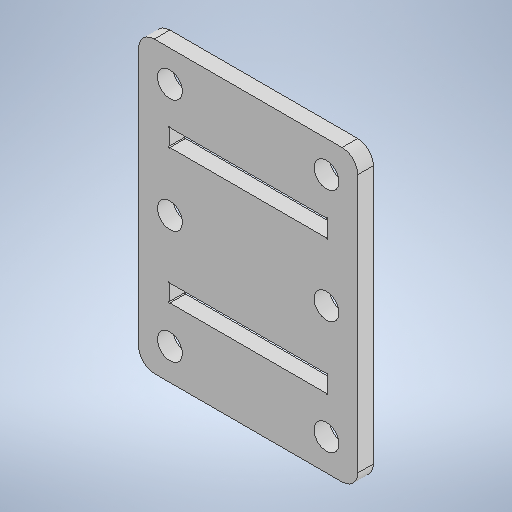
# Autodesk Inventor part: plate_ppp
Saved by Autodesk Inventor 2025.3 (Build 293356000, 356)
## iProperties
Created: 2026-10-27
Part Number: plate_ppp
Material: 一般
Document SubType Name: Modeling
Designer: yunto
Density: 1 g/cm^3
Appearance: 既定
Author: yunto
Autodesk Inventor part; units mm, degrees
ref_plane "YZ Plane" through (0, 0, 0) normal (1, 0, 0) x (0, 1, 0)
ref_plane "XZ Plane" through (0, 0, 0) normal (0, 1, 0) x (-1, 0, 0)
ref_plane "XY Plane" through (0, 0, 0) normal (0, 0, 1) x (1, 0, 0)
sketch "スケッチ1" plane through (0, 0, 0) normal (0, 0, 1) x (1, 0, 0)
  line L0 (14, -18.5) -> (-14, -18.5)
  line L1 (-14, -18.5) -> (-14, 18.5)
  line L2 (-14, 18.5) -> (14, 18.5)
  line L3 (14, 18.5) -> (14, -18.5)
  line L4 (14, -18.5) -> (-14, 18.5) construction
  line L5 (-14, -18.5) -> (14, 18.5) construction
  line L6 (-10, -14.5) -> (10, -14.5) construction
  line L7 (10, -14.5) -> (10, 14.5) construction
  line L8 (10, 14.5) -> (-10, 14.5) construction
  line L9 (-10, 14.5) -> (-10, -14.5) construction
  line L10 (-10, -14.5) -> (10, 14.5) construction
  line L11 (10, -14.5) -> (-10, 14.5) construction
  circle A0 centre (-10, 14.5) radius 1.6
  circle A1 centre (10, 14.5) radius 1.6
  circle A2 centre (-10, -14.5) radius 1.6
  circle A3 centre (10, -14.5) radius 1.6
  circle A4 centre (-10, 0) radius 1.6
  circle A5 centre (10, 0) radius 1.6
  line L12 (10.1, -9.7) -> (-10.1, -9.7)
  line L13 (-10.1, -9.7) -> (-10.1, 9.7)
  line L14 (-10.1, 9.7) -> (10.1, 9.7)
  line L15 (10.1, 9.7) -> (10.1, -9.7)
  line L16 (10.1, -9.7) -> (-10.1, 9.7) construction
  line L17 (-10.1, -9.7) -> (10.1, 9.7) construction
  line L18 (10.1, -7.5) -> (-10.1, -7.5)
  line L19 (-10.1, -7.5) -> (-10.1, 7.5)
  line L20 (-10.1, 7.5) -> (10.1, 7.5)
  line L21 (10.1, 7.5) -> (10.1, -7.5)
  line L22 (10.1, -7.5) -> (-10.1, 7.5) construction
  line L23 (-10.1, -7.5) -> (10.1, 7.5) construction
  circle A6 centre (10.1, 9.7) radius 0.1
  circle A7 centre (10.1, 7.5) radius 0.1
  circle A8 centre (-10.1, 9.7) radius 0.1
  circle A9 centre (-10.1, 7.5) radius 0.1
  circle A10 centre (-10.1, -7.5) radius 0.1
  circle A11 centre (10.1, -7.5) radius 0.1
  circle A12 centre (10.1, -9.7) radius 0.1
  circle A13 centre (-10.1, -9.7) radius 0.1
  point P0 (0, 0)
  point P1 (10.1, -7.5)
  point P2 (10.1, -7.6)
  point P3 (10.1, -9.6)
  point P4 (10, -9.7)
  point P5 (-10, -9.7)
  point P6 (-10.1, -9.6)
  point P7 (-10.1, -7.6)
  point P8 (-10, -7.5)
  point P9 (10, -7.5)
  point P10 (10, 7.5)
  point P11 (-10, 7.5)
  point P12 (-10.1, 7.6)
  point P13 (-10.1, 9.6)
  point P14 (-10, 9.7)
  point P15 (10, 9.7)
  point P16 (10.1, 9.6)
  point P17 (10.1, 7.6)
  dimension "d0" = 3.2
  dimension "d1" = 20
  dimension "d2" = 29
  dimension "d3" = 37
  dimension "d4" = 28
  dimension "d5" = 19.4
  dimension "d6" = 20.2
  dimension "d9" = 2.2
  dimension "d11" = 0.2
  constraints: 48 end point, 14 centre point, 12 equal radius, 11 coincident, 10 midpoint, 8 parallel, 4 horizontal, 4 perpendicular, 3 point on line
  measures "d0" diameter of A0
  measures "d1" distance of L7.end L8.end
  measures "d2" distance of L8.end L6.start
  measures "d3" distance of L0.end L1.end
  measures "d4" distance of L1.end L2.end
  measures "d5" distance of L12.end L13.end
  measures "d6" distance of L13.end L14.end
  measures "d9" distance between parallel lines of L14 L20
  measures "d11" diameter of A6
extrude "押し出し1" add sketch "スケッチ1" along normal blind 2 contours L0 L1 L2 L3 | A4 L13 A9 L20 A7 L15 A5 A11 L18 A10
fillet "フィレット1" radius 2 4 edges at (14, 18.5, 1) (14, -18.5, 1) (-14, -18.5, 1) (-14, 18.5, 1)
